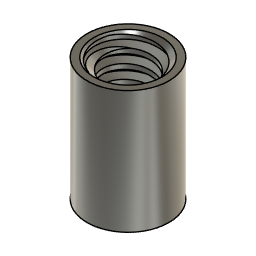
Dust Pan (Autodesk Fusion 360 archive; units mm, degrees)
design "Weld On Broom Handle Socket"
Autodesk Fusion 360 part; units mm, degrees
sketch "Sketch3" plane through (0, 0, 0) normal (0, 0, 1) x (-1, 0, 0)
  circle A0 centre (0, 0) radius 12.7
  dimension "d44" = 25.4
  constraint coincident A0.centre origin
  measures "d44" diameter of A0
extrude "Extrude3" add sketch "Sketch3" along normal blind 76.2
hole "Hole2" at (-0.0643, 0.214, 76.2) direction (0, 0, -1) diameter 14.9352 end through all
ref_plane "WorkPlane4" through (0, 0, 15.875) normal (0, 1, 0) x (0, 0, 1)
sketch "Sketch5" plane through (0, 0, 76.2) normal (0, 0, 1) x (-1, 0, 0)
  circle A0 centre (0, 0) radius 12.7
extrude "Extrude4" cut sketch "Sketch5" against normal blind 38.1
sketch "Sketch4" plane through (0, 0, 0) normal (0, 1, 0) x (1, 0, 0)
  line L0 (0, 15.875) -> (0, -47.625) construction
  line L1 (0, -224.4232) -> (0, -194.1795)
  line L2 (0, -194.1795) -> (26.2905, -224.4232)
  line L3 (26.2905, -224.4232) -> (0, -224.4232)
  line L4 (0, -206.375) -> (10.6014, -206.375) construction
  line L5 (-12.7, 0) -> (-12.7, -38.1) construction
  line L6 (12.7, -38.1) -> (12.7, 0) construction
  line L7 (-7.5224, -1.8473) -> (-7.5224, -0.308) construction
  spline S0 degree 3 poles (-7.5224, -0.308) (-7.909, -0.2071) (-8.3068, -0.1034) (-8.7037, 0) knots -0.247121 -0.247121 -0.247121 -0.247121 -0.128124 -0.128124 -0.128124 -0.128124 construction
  line L8 (-8.7037, 0) -> (-12.7, 0) construction
  line L9 (-12.7, -38.1) -> (-8.7037, -38.1) construction
  spline S1 degree 3 poles (-8.7037, -38.1) (-9.0844, -38.0008) (-9.4642, -37.902) (-9.8776, -37.7945) (-9.9228, -37.7827) (-9.968, -37.771) knots -0.128142 -0.128142 -0.128142 -0.128142 -0.013997 -0.013997 0 0 0 0 construction
  line L10 (-9.968, -37.771) -> (-9.968, -36.3414) construction
  spline S2 degree 3 poles (-9.968, -36.3414) (-9.2156, -36.148) (-8.4162, -35.9428) (-7.6132, -35.7372) (-7.5678, -35.7256) (-7.5224, -35.714) knots -0.248673 -0.248673 -0.248673 -0.248673 -0.014047 -0.014047 0 0 0 0 construction
  line L11 (-7.5224, -35.714) -> (-7.5224, -34.1747) construction
  spline S3 degree 3 poles (-7.5224, -34.1747) (-8.2798, -33.977) (-9.0803, -33.7685) (-9.8776, -33.5612) (-9.9228, -33.5494) (-9.968, -33.5377) knots -0.247148 -0.247148 -0.247148 -0.247148 -0.013997 -0.013997 0 0 0 0 construction
  line L12 (-9.968, -33.5377) -> (-9.968, -32.1081) construction
  spline S4 degree 3 poles (-9.968, -32.1081) (-9.2156, -31.9147) (-8.4162, -31.7094) (-7.6132, -31.5038) (-7.5678, -31.4922) (-7.5224, -31.4806) knots -0.248673 -0.248673 -0.248673 -0.248673 -0.014047 -0.014047 0 0 0 0 construction
  line L13 (-7.5224, -31.4806) -> (-7.5224, -29.9414) construction
  spline S5 degree 3 poles (-7.5224, -29.9414) (-8.2798, -29.7436) (-9.0803, -29.5352) (-9.8776, -29.3278) (-9.9228, -29.3161) (-9.968, -29.3043) knots -0.247148 -0.247148 -0.247148 -0.247148 -0.013997 -0.013997 0 0 0 0 construction
  line L14 (-9.968, -29.3043) -> (-9.968, -27.8748) construction
  spline S6 degree 3 poles (-9.968, -27.8748) (-9.2156, -27.6814) (-8.4162, -27.4761) (-7.6132, -27.2705) (-7.5678, -27.2589) (-7.5224, -27.2473) knots -0.248673 -0.248673 -0.248673 -0.248673 -0.014047 -0.014047 0 0 0 0 construction
  line L15 (-7.5224, -27.2473) -> (-7.5224, -25.708) construction
  spline S7 degree 3 poles (-7.5224, -25.708) (-8.2798, -25.5103) (-9.0803, -25.3018) (-9.8776, -25.0945) (-9.9228, -25.0827) (-9.968, -25.071) knots -0.247148 -0.247148 -0.247148 -0.247148 -0.013997 -0.013997 0 0 0 0 construction
  line L16 (-9.968, -25.071) -> (-9.968, -23.6414) construction
  spline S8 degree 3 poles (-9.968, -23.6414) (-9.2156, -23.448) (-8.4162, -23.2428) (-7.6132, -23.0372) (-7.5678, -23.0256) (-7.5224, -23.014) knots -0.248673 -0.248673 -0.248673 -0.248673 -0.014047 -0.014047 0 0 0 0 construction
  line L17 (-7.5224, -23.014) -> (-7.5224, -21.4747) construction
  spline S9 degree 3 poles (-7.5224, -21.4747) (-8.2798, -21.277) (-9.0803, -21.0685) (-9.8776, -20.8612) (-9.9228, -20.8494) (-9.968, -20.8377) knots -0.247148 -0.247148 -0.247148 -0.247148 -0.013997 -0.013997 0 0 0 0 construction
  line L18 (-9.968, -20.8377) -> (-9.968, -19.4081) construction
  spline S10 degree 3 poles (-9.968, -19.4081) (-9.2156, -19.2147) (-8.4162, -19.0094) (-7.6132, -18.8038) (-7.5678, -18.7922) (-7.5224, -18.7806) knots -0.248673 -0.248673 -0.248673 -0.248673 -0.014047 -0.014047 0 0 0 0 construction
  line L19 (-7.5224, -18.7806) -> (-7.5224, -17.2414) construction
  spline S11 degree 3 poles (-7.5224, -17.2414) (-8.2798, -17.0436) (-9.0803, -16.8352) (-9.8776, -16.6278) (-9.9228, -16.6161) (-9.968, -16.6043) knots -0.247148 -0.247148 -0.247148 -0.247148 -0.013997 -0.013997 0 0 0 0 construction
  line L20 (-9.968, -16.6043) -> (-9.968, -15.1748) construction
  spline S12 degree 3 poles (-9.968, -15.1748) (-9.2156, -14.9814) (-8.4162, -14.7761) (-7.6132, -14.5705) (-7.5678, -14.5589) (-7.5224, -14.5473) knots -0.248673 -0.248673 -0.248673 -0.248673 -0.014047 -0.014047 0 0 0 0 construction
  line L21 (-7.5224, -14.5473) -> (-7.5224, -13.008) construction
  spline S13 degree 3 poles (-7.5224, -13.008) (-8.2798, -12.8103) (-9.0803, -12.6018) (-9.8776, -12.3945) (-9.9228, -12.3827) (-9.968, -12.371) knots -0.247148 -0.247148 -0.247148 -0.247148 -0.013997 -0.013997 0 0 0 0 construction
  line L22 (-9.968, -12.371) -> (-9.968, -10.9414) construction
  spline S14 degree 3 poles (-9.968, -10.9414) (-9.2156, -10.748) (-8.4162, -10.5428) (-7.6132, -10.3372) (-7.5678, -10.3256) (-7.5224, -10.314) knots -0.248673 -0.248673 -0.248673 -0.248673 -0.014047 -0.014047 0 0 0 0 construction
  line L23 (-7.5224, -10.314) -> (-7.5224, -8.7747) construction
  spline S15 degree 3 poles (-7.5224, -8.7747) (-8.2798, -8.577) (-9.0803, -8.3685) (-9.8776, -8.1612) (-9.9228, -8.1494) (-9.968, -8.1377) knots -0.247148 -0.247148 -0.247148 -0.247148 -0.013997 -0.013997 0 0 0 0 construction
  line L24 (-9.968, -8.1377) -> (-9.968, -6.7081) construction
  spline S16 degree 3 poles (-9.968, -6.7081) (-9.2156, -6.5147) (-8.4162, -6.3094) (-7.6132, -6.1038) (-7.5678, -6.0922) (-7.5224, -6.0806) knots -0.248673 -0.248673 -0.248673 -0.248673 -0.014047 -0.014047 0 0 0 0 construction
  line L25 (-7.5224, -6.0806) -> (-7.5224, -4.5414) construction
  spline S17 degree 3 poles (-7.5224, -4.5414) (-8.2798, -4.3436) (-9.0803, -4.1352) (-9.8776, -3.9278) (-9.9228, -3.9161) (-9.968, -3.9043) knots -0.247148 -0.247148 -0.247148 -0.247148 -0.013997 -0.013997 0 0 0 0 construction
  line L26 (-9.968, -3.9043) -> (-9.968, -2.4748) construction
  spline S18 degree 3 poles (-9.968, -2.4748) (-9.2156, -2.2814) (-8.4162, -2.0761) (-7.6132, -1.8705) (-7.5678, -1.8589) (-7.5224, -1.8473) knots -0.248673 -0.248673 -0.248673 -0.248673 -0.014047 -0.014047 0 0 0 0 construction
  line L27 (7.3939, -36.2527) -> (7.3939, -37.792) construction
  spline S19 degree 3 poles (7.3939, -37.792) (7.7854, -37.8942) (8.1836, -37.998) (8.5752, -38.1) knots -0.251153 -0.251153 -0.251153 -0.251153 -0.130008 -0.130008 -0.130008 -0.130008 construction
  line L28 (8.5752, -38.1) -> (12.7, -38.1) construction
  line L29 (12.7, 0) -> (8.5752, 0) construction
  spline S20 degree 3 poles (8.5752, 0) (8.589, -0.0036) (8.6029, -0.0072) (9.0226, -0.1165) (9.4338, -0.2235) (9.8394, -0.329) knots -0.130008 -0.130008 -0.130008 -0.130008 -0.125723 -0.125723 0 0 0 0 construction
  line L30 (9.8394, -0.329) -> (9.8394, -1.7586) construction
  spline S21 degree 3 poles (9.8394, -1.7586) (9.4339, -1.8628) (9.0226, -1.9685) (8.2119, -2.1765) (7.7993, -2.2823) (7.3939, -2.386) knots -0.251429 -0.251429 -0.251429 -0.251429 -0.12555 -0.12555 0 0 0 0 construction
  line L31 (7.3939, -2.386) -> (7.3939, -3.9253) construction
  spline S22 degree 3 poles (7.3939, -3.9253) (7.7993, -4.0311) (8.2118, -4.1387) (9.0226, -4.3499) (9.4338, -4.4569) (9.8394, -4.5623) knots -0.251153 -0.251153 -0.251153 -0.251153 -0.125723 -0.125723 0 0 0 0 construction
  line L32 (9.8394, -4.5623) -> (9.8394, -5.9919) construction
  spline S23 degree 3 poles (9.8394, -5.9919) (9.4339, -6.0961) (9.0226, -6.2018) (8.2119, -6.4099) (7.7993, -6.5156) (7.3939, -6.6194) knots -0.251429 -0.251429 -0.251429 -0.251429 -0.12555 -0.12555 0 0 0 0 construction
  line L33 (7.3939, -6.6194) -> (7.3939, -8.1586) construction
  spline S24 degree 3 poles (7.3939, -8.1586) (7.7993, -8.2645) (8.2118, -8.372) (9.0226, -8.5832) (9.4338, -8.6902) (9.8394, -8.7957) knots -0.251153 -0.251153 -0.251153 -0.251153 -0.125723 -0.125723 0 0 0 0 construction
  line L34 (9.8394, -8.7957) -> (9.8394, -10.2252) construction
  spline S25 degree 3 poles (9.8394, -10.2252) (9.4339, -10.3295) (9.0226, -10.4351) (8.2119, -10.6432) (7.7993, -10.7489) (7.3939, -10.8527) knots -0.251429 -0.251429 -0.251429 -0.251429 -0.12555 -0.12555 0 0 0 0 construction
  line L35 (7.3939, -10.8527) -> (7.3939, -12.392) construction
  spline S26 degree 3 poles (7.3939, -12.392) (7.7993, -12.4978) (8.2118, -12.6054) (9.0226, -12.8165) (9.4338, -12.9235) (9.8394, -13.029) knots -0.251153 -0.251153 -0.251153 -0.251153 -0.125723 -0.125723 0 0 0 0 construction
  line L36 (9.8394, -13.029) -> (9.8394, -14.4586) construction
  spline S27 degree 3 poles (9.8394, -14.4586) (9.4339, -14.5628) (9.0226, -14.6685) (8.2119, -14.8765) (7.7993, -14.9823) (7.3939, -15.086) knots -0.251429 -0.251429 -0.251429 -0.251429 -0.12555 -0.12555 0 0 0 0 construction
  line L37 (7.3939, -15.086) -> (7.3939, -16.6253) construction
  spline S28 degree 3 poles (7.3939, -16.6253) (7.7993, -16.7311) (8.2118, -16.8387) (9.0226, -17.0499) (9.4338, -17.1569) (9.8394, -17.2623) knots -0.251153 -0.251153 -0.251153 -0.251153 -0.125723 -0.125723 0 0 0 0 construction
  line L38 (9.8394, -17.2623) -> (9.8394, -18.6919) construction
  spline S29 degree 3 poles (9.8394, -18.6919) (9.4339, -18.7961) (9.0226, -18.9018) (8.2119, -19.1099) (7.7993, -19.2156) (7.3939, -19.3194) knots -0.251429 -0.251429 -0.251429 -0.251429 -0.12555 -0.12555 0 0 0 0 construction
  line L39 (7.3939, -19.3194) -> (7.3939, -20.8586) construction
  spline S30 degree 3 poles (7.3939, -20.8586) (7.7993, -20.9645) (8.2118, -21.072) (9.0226, -21.2832) (9.4338, -21.3902) (9.8394, -21.4957) knots -0.251153 -0.251153 -0.251153 -0.251153 -0.125723 -0.125723 0 0 0 0 construction
  line L40 (9.8394, -21.4957) -> (9.8394, -22.9252) construction
  spline S31 degree 3 poles (9.8394, -22.9252) (9.4339, -23.0295) (9.0226, -23.1351) (8.2119, -23.3432) (7.7993, -23.4489) (7.3939, -23.5527) knots -0.251429 -0.251429 -0.251429 -0.251429 -0.12555 -0.12555 0 0 0 0 construction
  line L41 (7.3939, -23.5527) -> (7.3939, -25.092) construction
  spline S32 degree 3 poles (7.3939, -25.092) (7.7993, -25.1978) (8.2118, -25.3054) (9.0226, -25.5165) (9.4338, -25.6235) (9.8394, -25.729) knots -0.251153 -0.251153 -0.251153 -0.251153 -0.125723 -0.125723 0 0 0 0 construction
  line L42 (9.8394, -25.729) -> (9.8394, -27.1586) construction
  spline S33 degree 3 poles (9.8394, -27.1586) (9.4339, -27.2628) (9.0226, -27.3685) (8.2119, -27.5765) (7.7993, -27.6823) (7.3939, -27.786) knots -0.251429 -0.251429 -0.251429 -0.251429 -0.12555 -0.12555 0 0 0 0 construction
  line L43 (7.3939, -27.786) -> (7.3939, -29.3253) construction
  spline S34 degree 3 poles (7.3939, -29.3253) (7.7993, -29.4311) (8.2118, -29.5387) (9.0226, -29.7499) (9.4338, -29.8569) (9.8394, -29.9623) knots -0.251153 -0.251153 -0.251153 -0.251153 -0.125723 -0.125723 0 0 0 0 construction
  line L44 (9.8394, -29.9623) -> (9.8394, -31.3919) construction
  spline S35 degree 3 poles (9.8394, -31.3919) (9.4339, -31.4961) (9.0226, -31.6018) (8.2119, -31.8099) (7.7993, -31.9156) (7.3939, -32.0194) knots -0.251429 -0.251429 -0.251429 -0.251429 -0.12555 -0.12555 0 0 0 0 construction
  line L45 (7.3939, -32.0194) -> (7.3939, -33.5586) construction
  spline S36 degree 3 poles (7.3939, -33.5586) (7.7993, -33.6645) (8.2118, -33.772) (9.0226, -33.9832) (9.4338, -34.0902) (9.8394, -34.1957) knots -0.251153 -0.251153 -0.251153 -0.251153 -0.125723 -0.125723 0 0 0 0 construction
  line L46 (9.8394, -34.1957) -> (9.8394, -35.6252) construction
  spline S37 degree 3 poles (9.8394, -35.6252) (9.4339, -35.7295) (9.0226, -35.8351) (8.2119, -36.0432) (7.7993, -36.1489) (7.3939, -36.2527) knots -0.251429 -0.251429 -0.251429 -0.251429 -0.12555 -0.12555 0 0 0 0 construction
  line L47 (0, -47.625) -> (0, -27.2082)
  line L48 (0, -27.2082) -> (19.8725, -47.625)
  line L49 (19.8725, -47.625) -> (0, -47.625)
  point P0 (10.6014, -38.1)
  dimension "d31" = 41
  dimension "d45" = 0.762
  constraint vertical L1
  constraint perpendicular L1 L3
  constraint coincident L1 L4.start
  constraint coincident L2 L4.end
  constraint perpendicular L1 L4
  constraint coincident L0 L1.start
  constraint perpendicular L28 L47
  constraint perpendicular L0 L49
  constraint coincident L0.end L47.start
  constraint coincident L28 P0
  constraint coincident L48 P0
  measures "d31" angle of L1 L2
  measures "d45" distance of L46 P0
revolve "Revolve2" cut sketch "Sketch4" angle 360 about axis through (0, 0, -15.875) along (0, 0, 1) contours L47 L48 L49
ref_plane "WorkPlane5" through (0, 0, 19.05) normal (0, 0, 1) x (-1, 0, 0)
mirror "Mirror2" about plane through (0, 0, 19.05) normal (0, 0, 1) of "Revolve2"
equation "thickness_Ref = 0.075 \""
equation "d23 = 3\""
equation "d26 = 0.588 \""
equation "d28 = 0.00 \""
equation "d29 = 0.068 \""
equation "d31 = 41 °"
equation "d32 = -1.5 \""
equation "d44 = 1.00 \""
equation "d45 = 0.03 \""
equation "d48 = 0.004 \""
equation "d36 = d4"
